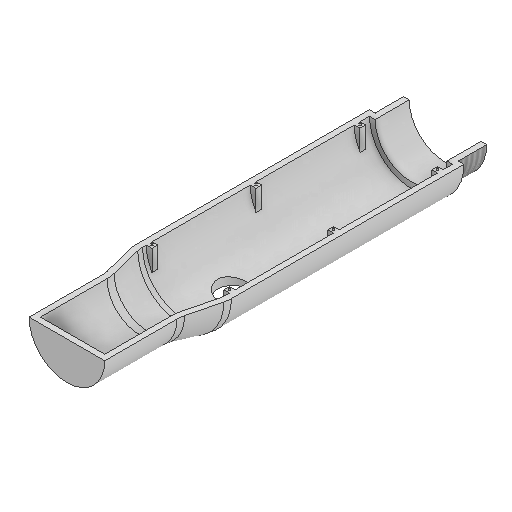
# Autodesk Inventor part: Blender_Upper Housing1
Saved by Autodesk Inventor 2027.1 (Build 311270010, 270A)
## iProperties
Created: 2026-10-20
Part Number: Blender_Upper Housing1
Material: Generic
Document SubType Name: Modeling
Designer: MSIPC
Density: 1 g/cm^3
Appearance: Default
Author: MSIPC
Autodesk Inventor part; units mm, degrees
ref_plane "YZ Plane" through (0, 0, 0) normal (1, 0, 0) x (0, 1, 0)
ref_plane "XY Plane" through (0, 0, 0) normal (0, 0, 1) x (1, 0, 0)
sketch "Sketch1" plane through (0, 0, 0) normal (0, 1, 0) x (-1, 0, 0)
  line L0 (-25, 15) -> (-25, 138)
  line L1 (-24.5593, 141.6094) -> (-20.4407, 158.2222)
  line L2 (-20, 161.8316) -> (-20, 200)
  line L3 (-20, 200) -> (-17, 200)
  line L4 (0, 200) -> (0, 0)
  arc A0 (-20.4407, 158.2222) -> (-20, 161.8316) centre (-35, 161.8316) ccw
  arc A1 (-24.5593, 141.6094) -> (-25, 138) centre (-10, 138) ccw
  line L5 (-22, 138) -> (-22, 18)
  line L6 (-17, 197) -> (-17, 161.8316)
  arc A2 (-17.5289, 157.5003) -> (-17, 161.8316) centre (-35, 161.8316) ccw
  line L7 (-17.5289, 157.5003) -> (-21.6474, 140.8875)
  arc A3 (-21.6474, 140.8875) -> (-22, 138) centre (-10, 138) ccw
  line L8 (-19, 18) -> (-19, 0)
  line L9 (-22, 18) -> (-19, 18)
  line L10 (-25, 15) -> (-22, 15)
  line L11 (-22, 15) -> (-22, 0)
  line L12 (-22, 0) -> (-19, 0)
  line L13 (-17, 200) -> (0, 200)
  line L14 (0, 197) -> (-17, 197)
  point P0 (-25, 139.8316)
  point P1 (-20, 160)
  dimension "d2" = 20
  dimension "d3" = 200
  dimension "d4" = 40
  dimension "d5" = 15
  dimension "d6" = 15
  dimension "d7" = 3
  dimension "d9" = 3
  dimension "d10" = 3
  dimension "d13" = 3
  dimension "d14" = 3
  dimension "d15" = 15
  dimension "d17" = 22
  dimension "d18" = 120
  dimension "d19" = 25
  dimension "d28" = 3
  constraints: 30 end point, 8 point on circle, 5 point on line, 4 centre point, 4 perpendicular, 4 tangent, 3 horizontal, 2 parallel, 1 vertical, 2 other
  measures "d2" distance of L2.end L4.start
  measures "d3" distance of L4.start L4.end
  measures "d4" distance of point (-20, 160) L2.end
  measures "d5" radius of A0
  measures "d6" radius of A1
  measures "d7" distance between parallel lines of L0 L5
  measures "d9" distance between parallel lines of L2 L6
  measures "d10" distance between parallel lines of L7 L1
  measures "d13" distance between parallel lines of L9 L10
  measures "d14" distance between parallel lines of L8 L11
  measures "d15" distance from line of L4.end L10
  measures "d17" distance between parallel lines of L4 L11
  measures "d18" distance of L5.start L5.end
  measures "d19" distance between parallel lines of L4 L0
  measures "d28" distance between parallel lines of L13 L14
revolve "Revolution1" add sketch "Sketch1" angle 360 about axis through (0, 0, 200) along (0, 0, -1)
thread "Thread1" size "M45x3" class "6g" standard "ANSI Metric M Profile" full length
ref_plane "Work Plane1" through (0, -25, 76.5) normal (0, 1, 0) x (-1, 0, 0)
sketch "Sketch4" plane through (0, -25, 76.5) normal (0, 1, 0) x (-1, 0, 0)
  circle A0 centre (0, 35.7219) radius 10
  point P0 (0, -76.5)
  dimension "d22" = 20
  constraints: 1 centre point
  measures "d22" diameter of A0
extrude "Extrusion1" add sketch "Sketch4" along normal up to surface round surface about axis through (0, 0, 78) along (0, 0, -1) radius 22 far side no
fillet "Fillet1" radius 2 3 edges at (-7.6112, -23.8132, 105.7358) (-7.6096, -23.8137, 118.7099) (10, -22.9129, 112.214)
sketch "Sketch5" plane through (0, 0, 200) normal (0, 0, 1) x (1, 0, 0)
  line L0 (32.2711, 0) -> (-33.1433, 0)
  line L1 (-33.1433, 0) -> (-33.1433, 30.3813)
  line L2 (-33.1433, 30.3813) -> (32.2711, 30.3813)
  line L3 (32.2711, 30.3813) -> (32.2711, 0)
  point P0 (0, 0)
  constraints: 8 end point, 2 parallel, 1 horizontal, 1 perpendicular
extrude "Extrusion2" cut sketch "Sketch5" against normal blind 219
sketch "Sketch6" plane through (-20, 0, 200) normal (0, 1, 0) x (1, 0, 0)
  line L0 (42, 62) -> (42, 182) projected
  line L1 (42, 177) -> (39, 177)
  line L2 (39, 177) -> (39, 174)
  line L3 (39, 174) -> (42, 174)
  line L4 (42, 174) -> (42, 177)
  line L5 (42, 182) -> (39, 182) projected
  line L6 (37, 3) -> (37, 38.1684) projected
  line L7 (3, 3) -> (37, 3) projected
  line L8 (42, 122) -> (39, 122)
  line L9 (39, 122) -> (39, 119)
  line L10 (39, 119) -> (42, 119)
  line L11 (42, 119) -> (42, 122)
  line L12 (42, 67) -> (39, 67)
  line L13 (39, 67) -> (39, 64)
  line L14 (39, 64) -> (42, 64)
  line L15 (42, 64) -> (42, 67)
  point P0 (20, 200)
  point P1 (39, 175.5)
  point P2 (40.5, 182)
  point P3 (42, 174)
  point P4 (39, 120.5)
  point P5 (39, 65.5)
  point P6 (42, 64)
  point P7 (42, 67)
  point P8 (42, 119)
  point P9 (42, 122)
  dimension "d29" = 3
  dimension "d30" = 3
  dimension "d31" = 5
  dimension "d39" = 55
  constraints: 24 end point, 2 midpoint, 2 parallel, 1 horizontal, 1 perpendicular, 1 point on line, 1 vertical, 18 other
  measures "d29" distance between parallel lines of L1 L3
  measures "d30" distance from line of L0 point (39, 175.5)
  measures "d31" distance from line of point (40.5, 182) L1
  measures "d39" distance of L1.start L8.start
extrude "Extrusion3" add sketch "Sketch6" against normal up to surface round surface about axis through (0, 0, 78) along (0, 0, -1) radius 22 far side no
sketch "Sketch7" plane through (-20, 0, 200) normal (0, 1, 0) x (1, 0, 0)
  circle A0 centre (40.5, 175.5) radius 0.5
  line L0 (42, 177) -> (39, 177) projected
  line L1 (39, 177) -> (39, 174) projected
  line L2 (20, 200) -> (20, 138.7981) construction
  circle A1 centre (40.5, 120.5) radius 0.5
  circle A2 centre (40.5, 65.5) radius 0.5
  point P0 (40.5, 177)
  dimension "d44" = 1
  dimension "d45" = 1.5
  dimension "d46" = 1.5
  dimension "d49" = 55
  constraints: 3 centre point, 2 end point, 2 vertical, 1 midpoint, 4 other
  measures "d44" diameter of A0
  measures "d45" distance of point (40.5, 177) A0.centre
  measures "d46" distance from line of L1 A0.centre
  measures "d49" distance of A0.centre A1.centre
extrude "Extrusion4" add sketch "Sketch7" along normal blind 1
fillet "Fillet2" radius 0.2 3 edges at (20, 1, 79.5) (20, 1, 24.5) (20, 1, 134.5)
mirror "Mirror2" about plane through (0, 0, 0) normal (1, 0, 0) of "Extrusion3", "Extrusion4", "Fillet2"
sketch "Sketch8" plane through (0, -25, 76.5) normal (0, -1, 0) x (1, 0, 0)
  arc A0 (-8.4984, 40.9924) -> (-8.4984, 30.4514) centre (0, 35.7219) ccw projected
  circle A1 centre (0, 35.7219) radius 8
  point P0 (0, -76.5)
  dimension "d57" = 16
  constraints: 1 centre point, 1 coincident
  measures "d57" diameter of A1
extrude "Extrusion5" cut sketch "Sketch8" against normal blind 10
body "Solid1"
